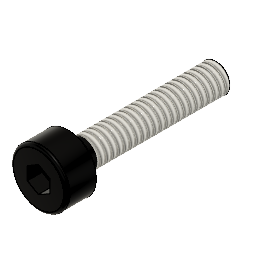
cad of ender 3v3 se head in fusion 360 ffile an .step v7 (Autodesk Fusion 360 archive; units mm, degrees)
design "Tornillo de cabeza hexagonal hueca ISO 4762 - M2 x 10 Acero 4.6 Negro"
description: Tornillo de cabeza hexagonal hueca ISO 4762 - M2 x 10
part number: ISO 4762 - M2 x 10 Acero 4.6 Negro
Autodesk Fusion 360 part; units mm, degrees
sketch "Sketch1" plane through (0, 0, 0) normal (0, 1, 0) x (1, 0, 0)
  line L0 (-1, 0) -> (-1, 10)
  line L1 (-1, 10) -> (0, 10)
  line L2 (0, 10) -> (0, -2)
  line L3 (-1, 0) -> (-1.9, 0)
  line L4 (-1.9, 0) -> (-1.9, -2)
  line L5 (-1.9, -2) -> (0, -2)
  dimension "d9" = 2
  dimension "d66" = 3.8
  dimension "d106" = 2
  dimension "d107" = 10
  constraint perpendicular L0 L1
  constraint collinear origin L1.end L2.end
  constraint perpendicular L0 L3
  constraint coincident origin L3
  constraint vertical L0
  constraint vertical L2
  constraint parallel L2 L4
  constraint coincident L2 L5.end
  constraint perpendicular L2 L5
  measures "d106" distance of L3 L5
  measures "d107" distance of origin L1
revolve "Revolve1" add sketch "Sketch1" angle 360 about axis through (0, 0, -10) along (0, 0, 1)
ref_plane "WorkPlane1" through (0, 0, 2) normal (0, 0, 1) x (1, 0, 0)
sketch "Sketch6" plane through (0, 0, 2) normal (0, 0, 1) x (1, 0, 0)
  line L0 (-0.75, 0) -> (0.75, 0) construction
  line L1 (0, 0) -> (-0.75, 0.433)
  line L2 (-0.75, -0.433) -> (-0.75, 0.433)
  line L3 (-0.75, -0.433) -> (0, 0)
  dimension "d104" = 150
  dimension "d108" = 1.5
  constraint horizontal L0
  constraint midpoint L1.start L0
  constraint coincident L1.start L3.end
  constraint perpendicular L0 L2
  constraint midpoint L0.start L2
  constraint coincident L1.end L2.end
  measures "d104" angle of L0 L1
  measures "d108" distance of L0.end L2
extrude "Extrude1" cut sketch "Sketch6" against normal blind 1
pattern_circular "C-Pattern1" count 6 over 360 about axis through (0, 0, 1.75) along (0, 0, 1) of "Extrude1"
extrude "Extrude2" cut 1 faces at (0, 0.2887, 1) along direction (0, 0, -1) blind 1 draft -85
fillet "Fillet4" radius 0.2 1 edges at (-1.7714, 0.6871, 2)
thread "Thread3" "ISO Metric profile 2.0 M2x0.4 M2x0.4 6g" major diameter 1.9335 minor diameter 1.478 pitch 0.4 angle 60 resizes the face on face at (-0.995, 0.0996, -3.3333) from (0, 0, -1) to (0, 0, -10)
sketch "Sketch7" plane through (0, 0, 0) normal (0, 1, 0) x (1, 0, 0)
  line L0 (-1.02, 10) -> (-1.02, 9.8)
  line L1 (-1.02, 9.8) -> (-0.82, 10)
  line L2 (0, 10) -> (0, -2)
  line L3 (-1.02, 10) -> (0, 10)
  dimension "d101" = 45
  dimension "d112" = 0.2
  dimension "d113" = 1.02
  constraint coincident L2.start L3.end
  constraint perpendicular L2 L3
  constraint coincident L1.end L3
  constraint perpendicular L0 L3
  measures "d101" angle of L0 L1
  measures "d112" distance of L0.end L3
  measures "d113" distance of L0 L2.start
revolve "Revolve3" cut sketch "Sketch7" angle 360 about axis through (0, 0, 1.75) along (0, 0, 1)
equation "d9 = adsk_nomdia"
equation "adsk_nomlen = 10.00 mm"
equation "adsk_headh = 2.00 mm"
equation "adsk_headdia = 3.80 mm"
equation "adsk_nomdia = 2.00 mm"
equation "adsk_philwidth = 1.50 mm"
equation "d31 = -adsk_phildepth"
equation "adsk_phildepth = 1.00 mm"
equation "d66 = adsk_headdia"
equation "d71 = adsk_headh"
equation "d76 = -adsk_phildepth"
equation "adsk_thrlen = 9.00 mm"
equation "d86 = adsk_nomdia * 0.1"
equation "adsk_startang = 45.00 deg"
equation "d101 = adsk_startang"
equation "adsk_pitch1 = 0.40 mm"
equation "adsk_startlen = 0.20 mm"
equation "d106 = adsk_headh"
equation "d107 = adsk_nomlen"
equation "d108 = adsk_philwidth"
equation "d112 = adsk_startlen"
equation "d113 = adsk_nomdia * 0.51"
equation "d115 = min(adsk_thrlen; adsk_nomlen - 0.001 mm)"

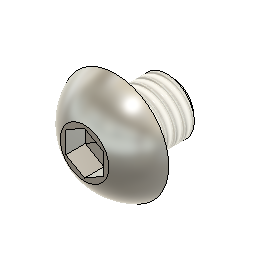
design "Tornillo brochado de cabeza de botón hueca hexagonal ASME B18.3.4M - M3 x 0.5 x 3 Acero grado 2 Normal"
description: Tornillo brochado de cabeza de botón hueca hexagonal ASME B18.3.4M - M3 x 0.5 x 3
part number: BHSBHCS ASME B18.3.4M - M3 x 0.5 x 3 Acero grado 2 Normal
Autodesk Fusion 360 part; units mm, degrees
sketch "Sketch1" plane through (0, 0, 0) normal (0, 1, 0) x (1, 0, 0)
  line L0 (-1.5, 0) -> (-1.5, 3)
  line L1 (-1.5, 3) -> (0, 3)
  line L2 (0, 3) -> (0, -1.65)
  line L3 (-1.5, 0) -> (-2.85, 0)
  line L4 (0, -1.65) -> (-1.3, -1.65)
  arc A0 (-2.85, 0) -> (-1.3, -1.65) centre (0, 1.1242) ccw
  dimension "d9" = 3
  dimension "d66" = 5.7
  dimension "d98" = 2.6
  dimension "d105" = 1.65
  dimension "d106" = 3
  constraint perpendicular L0 L1
  constraint perpendicular L0 L3
  constraint coincident origin L3
  constraint vertical L0
  constraint vertical L2
  constraint coincident origin L2
  constraint perpendicular L2 L4
  constraint coincident L2 A0.centre
  measures "d105" distance of L3 L4
  measures "d106" distance of origin L1
revolve "Revolve1" add sketch "Sketch1" angle 360 about axis through (0, 0, -3) along (0, 0, 1)
ref_plane "WorkPlane1" through (0, 0, 1.65) normal (0, 0, 1) x (1, 0, 0)
sketch "Sketch6" plane through (0, 0, 1.65) normal (0, 0, 1) x (1, 0, 0)
  line L0 (-1, 0) -> (1, 0) construction
  line L1 (0, 0) -> (-1, 0.5774)
  line L2 (-1, -0.5774) -> (-1, 0.5774)
  line L3 (-1, -0.5774) -> (0, 0)
  dimension "d91" = 150
  dimension "d107" = 2
  constraint horizontal L0
  constraint midpoint L1.start L0
  constraint coincident L1.start L3.end
  constraint perpendicular L0 L2
  constraint midpoint L0.start L2
  constraint coincident L1.end L2.end
  measures "d91" angle of L0 L1
  measures "d107" distance of L0.end L2
extrude "Extrude1" cut sketch "Sketch6" against normal blind 1.04
pattern_circular "C-Pattern1" count 6 over 360 about axis through (0, 0, 1.75) along (0, 0, 1) of "Extrude1"
extrude "Extrude2" cut 1 faces at (0, 0, 0.61) along direction (0, 0, -1) blind 1.04 draft -85
fillet "Fillet5" radius 0.1 1 edges at (-1.3985, 0.5424, 0)
thread "Thread5" "ANSI Metric M Profile 3.0 M3x0.5 M3x0.5 4g6g" major diameter 2.927 minor diameter 2.369 pitch 0.5 angle 60 resizes the face on face at (-1.4925, 0.1494, -2.0333) from (0, 0, -1) to (0, 0, -3)
sketch "Sketch5" plane through (0, 0, 0) normal (0, 1, 0) x (1, 0, 0)
  line L0 (0, 3) -> (0, -1.65)
  line L1 (0, 3) -> (-1.53, 3)
  line L2 (-1.53, 3) -> (-1.53, 2.6933)
  line L3 (-1.53, 2.6933) -> (-1.1933, 3)
  dimension "d108" = 0.3067
  dimension "d109" = 1.1933
  dimension "d110" = 1.53
  constraint coincident L0.start L1.start
  constraint perpendicular L1 L2
  constraint coincident L1 L3.end
  measures "d108" distance of L1 L2.end
  measures "d109" distance of L0 L3.end
  measures "d110" distance of L0 L2
revolve "Revolve2" cut sketch "Sketch5" angle 360 about axis through (0, 0, -3) along (0, 0, 1)
equation "d9 = adsk_nomdia"
equation "adsk_nomlen = 3.00 mm"
equation "adsk_headh = 1.65 mm"
equation "adsk_headdia = 5.70 mm"
equation "adsk_nomdia = 3.00 mm"
equation "adsk_philwidth = 2.00 mm"
equation "d31 = -adsk_phildepth"
equation "adsk_phildepth = 1.04 mm"
equation "d66 = adsk_headdia"
equation "d71 = adsk_headh"
equation "d76 = -adsk_phildepth"
equation "adsk_thrlen = 2.00 mm"
equation "adsk_endpointdia = 2.38655 mm"
equation "adsk_startlen = 0.306725 mm"
equation "d98 = adsk_philwidth * 1.3"
equation "adsk_midfillet = 0.10 mm"
equation "d104 = adsk_midfillet"
equation "d105 = adsk_headh"
equation "d106 = adsk_nomlen"
equation "d107 = adsk_philwidth"
equation "d108 = adsk_startlen"
equation "d109 = adsk_endpointdia / 2"
equation "d110 = adsk_nomdia * 0.51"
equation "d116 = min(adsk_thrlen; adsk_nomlen - adsk_midfillet - 0.001 mm)"

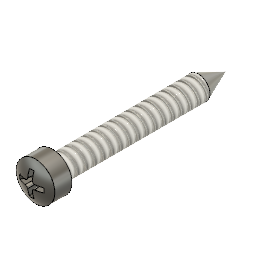
design "Tornillo autorroscante taladrado con hueco cruciforme de tipo I ANSI B18.6.4 2-32 x 0.625 Tipo AB Acero grado 2 Normal"
description: Tornillo autorroscante taladrado con hueco cruciforme de tipo I ANSI B18.6.4 2-32 x 0.625 Tipo AB
part number: CRFHTSTATI ANSI B18.6.4 - 2-32 x 5/8 Acero grado 2 Normal
Autodesk Fusion 360 part; units mm, degrees
sketch "Sketch1" plane through (0, 0, 0) normal (0, 1, 0) x (1, 0, 0)
  line L0 (-1.0922, 0) -> (-1.0922, 15.875)
  line L1 (-1.0922, 15.875) -> (0, 15.875)
  line L2 (0, 15.875) -> (0, -2.1082)
  line L3 (-1.0922, 0) -> (-1.778, 0)
  line L4 (-1.778, 0) -> (-1.778, -1.5748)
  arc A0 (-1.778, -1.5748) -> (0, -2.1082) centre (0, 1.1218) ccw
  dimension "d9" = 2.1844
  dimension "d66" = 3.556
  dimension "d113" = 2.1082
  dimension "d115" = 15.875
  constraint perpendicular L0 L1
  constraint perpendicular L0 L3
  constraint coincident origin L3
  constraint vertical L0
  constraint vertical L2
  constraint coincident L2 A0.centre
  constraint perpendicular L3 L4
  constraint coincident origin L2
  measures "d113" distance of L2.end L3
  measures "d115" distance of origin L1
revolve "Revolve1" add sketch "Sketch1" angle 360 about axis through (0, 0, -15.875) along (0, 0, 1) makes body 1
ref_plane "WorkPlane1" through (0, 0, 2.1082) normal (0, 0, 1) x (1, 0, 0)
sketch "Sketch2" plane through (0, 0, 2.1082) normal (0, 0, 1) x (1, 0, 0)
  line L0 (-0.2159, 0.2159) -> (-1.2446, 0.2159)
  line L1 (-1.2446, 0.2159) -> (-1.2446, -0.2159)
  line L2 (-0.2159, -0.2159) -> (-1.2446, -0.2159)
  line L3 (-0.2159, -0.2159) -> (-0.2159, -1.2446)
  line L4 (-0.2159, -1.2446) -> (0.2159, -1.2446)
  line L5 (0.2159, -0.2159) -> (0.2159, -1.2446)
  line L6 (0.2159, -0.2159) -> (1.2446, -0.2159)
  line L7 (1.2446, -0.2159) -> (1.2446, 0.2159)
  line L8 (0.2159, 0.2159) -> (1.2446, 0.2159)
  line L9 (0.2159, 0.2159) -> (0.2159, 1.2446)
  line L10 (0.2159, 1.2446) -> (-0.2159, 1.2446)
  line L11 (-0.2159, 0.2159) -> (-0.2159, 1.2446)
  point P0 (-1.2446, 0)
  dimension "d107" = 0.4318
  dimension "d109" = 360
  dimension "d110" = 2.4892
  constraint vertical L1
  constraint coincident L1.end L2.end
  constraint midpoint L1 P0
  constraint horizontal L0
  constraint horizontal L2
  constraint vertical L0.start L2.start
  constraint coincident L0.start L11.start
  measures "d107" distance of L0 L2
  measures "d110" distance of L1 L7
extrude "Extrude1" add sketch "Sketch2" against normal blind 1.27 draft -4 separate body makes body 2
draft "Draft1" angle -30 neutral plane through (0, 0, 2.1082) pull (0, 0, 1) 4 faces at (-1.215, -0.0424, 1.6849) (0.0424, -1.215, 1.6849) (1.215, 0.0424, 1.6849) (-0.0424, 1.215, 1.6849) on bodies 2
fillet "Fillet3" radius 0.2159 4 edges at (-0.1715, -0.1715, 1.4732) (-0.1715, 0.1715, 1.4732) (0.1715, 0.1715, 1.4732) (0.1715, -0.1715, 1.4732) on bodies 2
combine "Combine1" operation cut target body 1 tool bodies 2
thread "Thread1" "Inch Tapping Threads 0.086 2-32 2-32 2B" major diameter 2.159 minor diameter 1.5748 pitch 0.7937 angle 60 resizes the face on face at (-1.0908, 0.0544, -5.2917) on bodies 1
sketch "Sketch5" plane through (0, 0, 0) normal (0, 1, 0) x (1, 0, 0)
  line L0 (-1.114, 13.2382) -> (0, 15.875)
  line L1 (-1.114, 13.2382) -> (-1.114, 15.875)
  line L2 (0, 15.875) -> (0, -2.1082)
  line L3 (-1.114, 15.875) -> (0, 15.875)
  dimension "d116" = 1.114
  dimension "d117" = 2.6368
  constraint coincident L0.end L2.start
  constraint coincident L0.end L3
  constraint perpendicular L2 L3
  constraint perpendicular L1 L3
  measures "d116" distance of L1 L0.end
  measures "d117" distance of L0.start L3
revolve "Revolve2" cut sketch "Sketch5" angle 360 about axis through (0, 0, -15.875) along (0, 0, 1) bodies 1
equation "d9 = adsk_nomdia"
equation "d31 = -adsk_phildepth"
equation "d66 = adsk_headdia"
equation "d71 = adsk_headh"
equation "adsk_nomlen = 0.625 in"
equation "adsk_headh = 0.083 in"
equation "adsk_headdia = 0.14 in"
equation "adsk_nomdia = 0.086 in"
equation "adsk_phildia = 0.098 in"
equation "adsk_philwidth = 0.017 in"
equation "adsk_phildepth = 0.05 in"
equation "adsk_startlen = 0.103811 in"
equation "adsk_ovalh = 0.021 in"
equation "d107 = adsk_philwidth"
equation "d110 = adsk_phildia"
equation "d112 = adsk_philwidth / 2"
equation "d113 = adsk_headh"
equation "d114 = ( adsk_headh ) - ( adsk_ovalh )"
equation "d115 = adsk_nomlen"
equation "d116 = adsk_nomdia * 0.51"
equation "d117 = adsk_startlen"

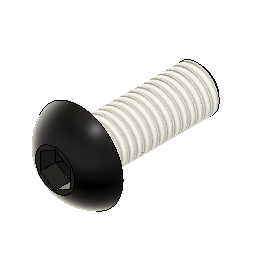
design "Tornillo brochado de cabeza de botón hueca hexagonal ASME B18.3.4M - M3 x 0.5 x 8 Acero grado 2 Negro"
description: Tornillo brochado de cabeza de botón hueca hexagonal ASME B18.3.4M - M3 x 0.5 x 8
part number: BHSBHCS ASME B18.3.4M - M3 x 0.5 x 8 Acero grado 2 Negro
Autodesk Fusion 360 part; units mm, degrees
sketch "Sketch1" plane through (0, 0, 0) normal (0, 1, 0) x (1, 0, 0)
  line L0 (-1.5, 0) -> (-1.5, 8)
  line L1 (-1.5, 8) -> (0, 8)
  line L2 (0, 8) -> (0, -1.65)
  line L3 (-1.5, 0) -> (-2.85, 0)
  line L4 (0, -1.65) -> (-1.3, -1.65)
  arc A0 (-2.85, 0) -> (-1.3, -1.65) centre (0, 1.1242) ccw
  dimension "d9" = 3
  dimension "d66" = 5.7
  dimension "d98" = 2.6
  dimension "d105" = 1.65
  dimension "d106" = 8
  constraint perpendicular L0 L1
  constraint perpendicular L0 L3
  constraint coincident origin L3
  constraint vertical L0
  constraint vertical L2
  constraint coincident origin L2
  constraint perpendicular L2 L4
  constraint coincident L2 A0.centre
  measures "d105" distance of L3 L4
  measures "d106" distance of origin L1
revolve "Revolve1" add sketch "Sketch1" angle 360 about axis through (0, 0, -8) along (0, 0, 1)
ref_plane "WorkPlane1" through (0, 0, 1.65) normal (0, 0, 1) x (1, 0, 0)
sketch "Sketch6" plane through (0, 0, 1.65) normal (0, 0, 1) x (1, 0, 0)
  line L0 (-1, 0) -> (1, 0) construction
  line L1 (0, 0) -> (-1, 0.5774)
  line L2 (-1, -0.5774) -> (-1, 0.5774)
  line L3 (-1, -0.5774) -> (0, 0)
  dimension "d91" = 150
  dimension "d107" = 2
  constraint horizontal L0
  constraint midpoint L1.start L0
  constraint coincident L1.start L3.end
  constraint perpendicular L0 L2
  constraint midpoint L0.start L2
  constraint coincident L1.end L2.end
  measures "d91" angle of L0 L1
  measures "d107" distance of L0.end L2
extrude "Extrude1" cut sketch "Sketch6" against normal blind 1.04
pattern_circular "C-Pattern1" count 6 over 360 about axis through (0, 0, 1.75) along (0, 0, 1) of "Extrude1"
extrude "Extrude2" cut 1 faces at (0, 0, 0.61) along direction (0, 0, -1) blind 1.04 draft -85
fillet "Fillet5" radius 0.1 1 edges at (-1.3985, 0.5424, 0)
thread "Thread5" "ANSI Metric M Profile 3.0 M3x0.5 M3x0.5 4g6g" major diameter 2.927 minor diameter 2.369 pitch 0.5 angle 60 resizes the face on face at (-1.4925, 0.1494, -5.3667) from (0, 0, -1) to (0, 0, -8)
sketch "Sketch5" plane through (0, 0, 0) normal (0, 1, 0) x (1, 0, 0)
  line L0 (0, 8) -> (0, -1.65)
  line L1 (0, 8) -> (-1.53, 8)
  line L2 (-1.53, 8) -> (-1.53, 7.6933)
  line L3 (-1.53, 7.6933) -> (-1.1933, 8)
  dimension "d108" = 0.3067
  dimension "d109" = 1.1933
  dimension "d110" = 1.53
  constraint coincident L0.start L1.start
  constraint perpendicular L1 L2
  constraint coincident L1 L3.end
  measures "d108" distance of L1 L2.end
  measures "d109" distance of L0 L3.end
  measures "d110" distance of L0 L2
revolve "Revolve2" cut sketch "Sketch5" angle 360 about axis through (0, 0, -8) along (0, 0, 1)
equation "d9 = adsk_nomdia"
equation "adsk_nomlen = 8.00 mm"
equation "adsk_headh = 1.65 mm"
equation "adsk_headdia = 5.70 mm"
equation "adsk_nomdia = 3.00 mm"
equation "adsk_philwidth = 2.00 mm"
equation "d31 = -adsk_phildepth"
equation "adsk_phildepth = 1.04 mm"
equation "d66 = adsk_headdia"
equation "d71 = adsk_headh"
equation "d76 = -adsk_phildepth"
equation "adsk_thrlen = 7.00 mm"
equation "adsk_endpointdia = 2.38655 mm"
equation "adsk_startlen = 0.306725 mm"
equation "d98 = adsk_philwidth * 1.3"
equation "adsk_midfillet = 0.10 mm"
equation "d104 = adsk_midfillet"
equation "d105 = adsk_headh"
equation "d106 = adsk_nomlen"
equation "d107 = adsk_philwidth"
equation "d108 = adsk_startlen"
equation "d109 = adsk_endpointdia / 2"
equation "d110 = adsk_nomdia * 0.51"
equation "d116 = min(adsk_thrlen; adsk_nomlen - adsk_midfillet - 0.001 mm)"

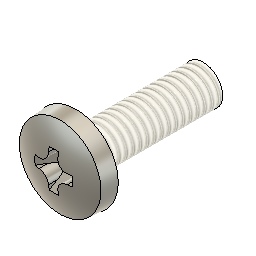
design "Tornillo de fijación JIS B 1111 - M2.5x8 Acero 4.6 Normal"
description: Tornillo de fijación JIS B 1111 - M2.5x8
Autodesk Fusion 360 part; units mm, degrees
sketch "Sketch1" plane through (0, 0, 0) normal (0, 1, 0) x (1, 0, 0)
  line L0 (0, -1.5) -> (0, 8)
  line L1 (-2.65, 0) -> (-2.5625, -1)
  line L2 (-2.65, 0) -> (-1.0691, 0)
  arc A0 (-2.5625, -1) -> (0, -1.5) centre (0, 5.3165) ccw
  line L3 (0, 8) -> (-1.25, 8)
  line L4 (-1.25, 8) -> (-1.25, 0.84)
  line L5 (-1.25, 0.84) -> (-1.0691, 0.165)
  line L6 (-1.0691, 0.165) -> (-1.0691, 0)
  dimension "d13" = 5
  dimension "d14" = 5.3
  dimension "d18" = 2.5
  dimension "d23" = 15
  dimension "d53" = 1.5
  dimension "d55" = 7.16
  dimension "d56" = 8
  dimension "d57" = 7.835
  dimension "d60" = 1
  constraint vertical L0
  constraint coincident origin L0
  constraint horizontal L2
  constraint coincident origin L2
  constraint coincident L0 A0.end
  constraint coincident L0 A0.centre
  constraint coincident L0.start A0.end
  constraint perpendicular L0 L3
  constraint perpendicular L3 L4
  constraint vertical L6
  constraint coincident L2.end L6.end
  measures "d13" angle of L0 L1
  measures "d23" angle of L4 L5
  measures "d53" distance of L0.start L2
  measures "d55" distance of L3 L4.end
  measures "d56" distance of L2 L3
  measures "d57" distance of L3 L5.end
  measures "d60" distance of L1.end L2
revolve "Revolve1" add sketch "Sketch1" angle 360 about axis through (0, 0, 1.5) along (0, 0, -1) makes body 1
fillet "Fillet2" radius 0.1 1 edges at (-0.9968, 0.3866, 0) on bodies 1
ref_plane "WorkPlane1" through (0, 0, 1.5) normal (0, 0, 1) x (1, 0, 0)
sketch "Sketch2" plane through (0, 0, 1.5) normal (0, 0, 1) x (1, 0, 0)
  line L0 (-1.25, 0) -> (1.25, 0) construction
  line L1 (0, -1.25) -> (0, 1.25) construction
  line L2 (-0.296, 1.25) -> (0.296, 1.25)
  line L3 (0.296, 1.25) -> (0.296, 0.296)
  line L4 (0.296, 0.296) -> (1.25, 0.296)
  line L5 (1.25, 0.296) -> (1.25, -0.296)
  line L6 (1.25, -0.296) -> (0.296, -0.296)
  line L7 (0.296, -0.296) -> (0.296, -1.25)
  line L8 (0.296, -1.25) -> (-0.296, -1.25)
  line L9 (-0.296, -1.25) -> (-0.296, -0.296)
  line L10 (-0.296, -0.296) -> (-1.25, -0.296)
  line L11 (-1.25, -0.296) -> (-1.25, 0.296)
  line L12 (-1.25, 0.296) -> (-0.296, 0.296)
  line L13 (-0.296, 0.296) -> (-0.296, 1.25)
  dimension "d58" = 0.592
  dimension "d59" = 0.592
  dimension "d61" = 2.5
  dimension "d62" = 2.5
  constraint horizontal L0
  constraint vertical L1
  constraint midpoint L0 L1
  constraint midpoint origin L1
  constraint perpendicular L1 L2
  constraint perpendicular L2 L3
  constraint perpendicular L3 L4
  constraint perpendicular L0 L5
  constraint perpendicular L5 L6
  constraint perpendicular L0 L7
  constraint perpendicular L7 L8
  constraint perpendicular L8 L9
  constraint perpendicular L7 L10
  constraint perpendicular L10 L11
  constraint perpendicular L11 L12
  constraint vertical L13
  constraint coincident L9 L12.end
  constraint coincident L3.end L7
  constraint coincident L6 L9.end
  constraint coincident L4 L12.end
  constraint midpoint L0.end L5
  constraint midpoint L1.start L8
  constraint midpoint L1.end L2
  constraint midpoint L0.start L11
  measures "d58" distance of L10 L12
  measures "d59" distance of L3 L13
  measures "d61" distance of L2 L8
  measures "d62" distance of L5 L11
extrude "Extrude1" add sketch "Sketch2" against normal blind 1.32 separate body makes body 2
draft "Draft1" angle -30 neutral plane through (0, 0, 1.5) pull (0, 0, 1) 4 faces at (0.0987, -1.25, 1.06) (-0.0987, 1.25, 1.06) (-1.25, -0.0987, 1.06) (1.25, 0.0987, 1.06) on bodies 2
fillet "Fillet1" radius 0.592 4 edges at (0.296, -0.296, 0.84) (-0.296, -0.296, 0.84) (-0.296, 0.296, 0.84) (0.296, 0.296, 0.84) on bodies 2
combine "Combine1" operation cut target body 1 tool bodies 2
thread "Thread1" "ISO Metric profile 2.5 M2.5x0.45 M2.5x0.45 6g" major diameter 2.43 minor diameter 1.9165 pitch 0.45 angle 60 resizes the face on face at (-1.2484, -0.0623, -5.6133) on bodies 1
equation "adsk_nomdia = 2.50 mm"
equation "adsk_nomlen = 8.00 mm"
equation "adsk_headdia = 5.30 mm"
equation "adsk_baseh = 1.00 mm"
equation "adsk_phildia = 2.50 mm"
equation "adsk_midfillet = 0.10 mm"
equation "adsk_thrlen = 7.16 mm"
equation "adsk_phildepth = 1.32 mm"
equation "adsk_thrrun = 0.675 mm"
equation "adsk_thrang = 15.00 deg"
equation "adsk_headang = 5.00 deg"
equation "d13 = adsk_headang"
equation "d14 = adsk_headdia"
equation "adsk_ovalh = 0.50 mm"
equation "d18 = adsk_nomdia"
equation "d23 = adsk_thrang"
equation "d32 = adsk_baseh + adsk_ovalh"
equation "adsk_philwidth = 0.592 mm"
equation "d43 = -adsk_phildepth"
equation "d48 = adsk_philwidth"
equation "d52 = adsk_midfillet"
equation "d53 = adsk_baseh + adsk_ovalh"
equation "d55 = adsk_thrlen"
equation "d56 = adsk_nomlen"
equation "d57 = adsk_thrlen + adsk_thrrun"
equation "d58 = adsk_philwidth"
equation "d59 = adsk_philwidth"
equation "d60 = adsk_baseh"
equation "d61 = adsk_phildia"
equation "d62 = adsk_phildia"

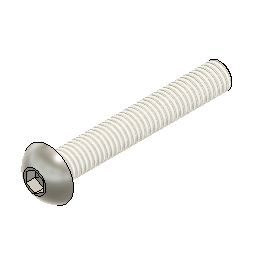
design "Tornillo brochado de cabeza de botón hueca hexagonal ASME B18.3.4M - M3 x 0.5 x 20 Acero grado 2 Normal"
description: Tornillo brochado de cabeza de botón hueca hexagonal ASME B18.3.4M - M3 x 0.5 x 20
part number: BHSBHCS ASME B18.3.4M - M3 x 0.5 x 20 Acero grado 2 Normal
Autodesk Fusion 360 part; units mm, degrees
sketch "Sketch1" plane through (0, 0, 0) normal (0, 1, 0) x (1, 0, 0)
  line L0 (-1.5, 0) -> (-1.5, 20)
  line L1 (-1.5, 20) -> (0, 20)
  line L2 (0, 20) -> (0, -1.65)
  line L3 (-1.5, 0) -> (-2.85, 0)
  line L4 (0, -1.65) -> (-1.3, -1.65)
  arc A0 (-2.85, 0) -> (-1.3, -1.65) centre (0, 1.1242) ccw
  dimension "d9" = 3
  dimension "d66" = 5.7
  dimension "d98" = 2.6
  dimension "d105" = 1.65
  dimension "d106" = 20
  constraint perpendicular L0 L1
  constraint perpendicular L0 L3
  constraint coincident origin L3
  constraint vertical L0
  constraint vertical L2
  constraint coincident origin L2
  constraint perpendicular L2 L4
  constraint coincident L2 A0.centre
  measures "d105" distance of L3 L4
  measures "d106" distance of origin L1
revolve "Revolve1" add sketch "Sketch1" angle 360 about axis through (0, 0, -20) along (0, 0, 1)
ref_plane "WorkPlane1" through (0, 0, 1.65) normal (0, 0, 1) x (1, 0, 0)
sketch "Sketch6" plane through (0, 0, 1.65) normal (0, 0, 1) x (1, 0, 0)
  line L0 (-1, 0) -> (1, 0) construction
  line L1 (0, 0) -> (-1, 0.5774)
  line L2 (-1, -0.5774) -> (-1, 0.5774)
  line L3 (-1, -0.5774) -> (0, 0)
  dimension "d91" = 150
  dimension "d107" = 2
  constraint horizontal L0
  constraint midpoint L1.start L0
  constraint coincident L1.start L3.end
  constraint perpendicular L0 L2
  constraint midpoint L0.start L2
  constraint coincident L1.end L2.end
  measures "d91" angle of L0 L1
  measures "d107" distance of L0.end L2
extrude "Extrude1" cut sketch "Sketch6" against normal blind 1.04
pattern_circular "C-Pattern1" count 6 over 360 about axis through (0, 0, 1.75) along (0, 0, 1) of "Extrude1"
extrude "Extrude2" cut 1 faces at (0, 0, 0.61) along direction (0, 0, -1) blind 1.04 draft -85
fillet "Fillet5" radius 0.1 1 edges at (-1.3985, 0.5424, 0)
thread "Thread5" "ANSI Metric M Profile 3.0 M3x0.5 M3x0.5 4g6g" major diameter 2.927 minor diameter 2.369 pitch 0.5 angle 60 resizes the face on face at (-1.4925, 0.1494, -6.7333) from (0, 0, -1) to (0, 0, -20)
sketch "Sketch5" plane through (0, 0, 0) normal (0, 1, 0) x (1, 0, 0)
  line L0 (0, 20) -> (0, -1.65)
  line L1 (0, 20) -> (-1.53, 20)
  line L2 (-1.53, 20) -> (-1.53, 19.6933)
  line L3 (-1.53, 19.6933) -> (-1.1933, 20)
  dimension "d108" = 0.3067
  dimension "d109" = 1.1933
  dimension "d110" = 1.53
  constraint coincident L0.start L1.start
  constraint perpendicular L1 L2
  constraint coincident L1 L3.end
  measures "d108" distance of L1 L2.end
  measures "d109" distance of L0 L3.end
  measures "d110" distance of L0 L2
revolve "Revolve2" cut sketch "Sketch5" angle 360 about axis through (0, 0, -20) along (0, 0, 1)
equation "d9 = adsk_nomdia"
equation "adsk_nomlen = 20.00 mm"
equation "adsk_headh = 1.65 mm"
equation "adsk_headdia = 5.70 mm"
equation "adsk_nomdia = 3.00 mm"
equation "adsk_philwidth = 2.00 mm"
equation "d31 = -adsk_phildepth"
equation "adsk_phildepth = 1.04 mm"
equation "d66 = adsk_headdia"
equation "d71 = adsk_headh"
equation "d76 = -adsk_phildepth"
equation "adsk_thrlen = 19.00 mm"
equation "adsk_endpointdia = 2.38655 mm"
equation "adsk_startlen = 0.306725 mm"
equation "d98 = adsk_philwidth * 1.3"
equation "adsk_midfillet = 0.10 mm"
equation "d104 = adsk_midfillet"
equation "d105 = adsk_headh"
equation "d106 = adsk_nomlen"
equation "d107 = adsk_philwidth"
equation "d108 = adsk_startlen"
equation "d109 = adsk_endpointdia / 2"
equation "d110 = adsk_nomdia * 0.51"
equation "d116 = min(adsk_thrlen; adsk_nomlen - adsk_midfillet - 0.001 mm)"

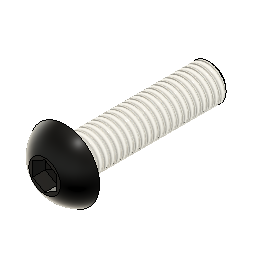
design "Tornillo brochado de cabeza de botón hueca hexagonal ASME B18.3.4M - M3 x 0.5 x 12 Acero grado 2 Negro"
description: Tornillo brochado de cabeza de botón hueca hexagonal ASME B18.3.4M - M3 x 0.5 x 12
part number: BHSBHCS ASME B18.3.4M - M3 x 0.5 x 12 Acero grado 2 Negro
Autodesk Fusion 360 part; units mm, degrees
sketch "Sketch1" plane through (0, 0, 0) normal (0, 1, 0) x (1, 0, 0)
  line L0 (-1.5, 0) -> (-1.5, 12)
  line L1 (-1.5, 12) -> (0, 12)
  line L2 (0, 12) -> (0, -1.65)
  line L3 (-1.5, 0) -> (-2.85, 0)
  line L4 (0, -1.65) -> (-1.3, -1.65)
  arc A0 (-2.85, 0) -> (-1.3, -1.65) centre (0, 1.1242) ccw
  dimension "d9" = 3
  dimension "d66" = 5.7
  dimension "d98" = 2.6
  dimension "d105" = 1.65
  dimension "d106" = 12
  constraint perpendicular L0 L1
  constraint perpendicular L0 L3
  constraint coincident origin L3
  constraint vertical L0
  constraint vertical L2
  constraint coincident origin L2
  constraint perpendicular L2 L4
  constraint coincident L2 A0.centre
  measures "d105" distance of L3 L4
  measures "d106" distance of origin L1
revolve "Revolve1" add sketch "Sketch1" angle 360 about axis through (0, 0, -12) along (0, 0, 1)
ref_plane "WorkPlane1" through (0, 0, 1.65) normal (0, 0, 1) x (1, 0, 0)
sketch "Sketch6" plane through (0, 0, 1.65) normal (0, 0, 1) x (1, 0, 0)
  line L0 (-1, 0) -> (1, 0) construction
  line L1 (0, 0) -> (-1, 0.5774)
  line L2 (-1, -0.5774) -> (-1, 0.5774)
  line L3 (-1, -0.5774) -> (0, 0)
  dimension "d91" = 150
  dimension "d107" = 2
  constraint horizontal L0
  constraint midpoint L1.start L0
  constraint coincident L1.start L3.end
  constraint perpendicular L0 L2
  constraint midpoint L0.start L2
  constraint coincident L1.end L2.end
  measures "d91" angle of L0 L1
  measures "d107" distance of L0.end L2
extrude "Extrude1" cut sketch "Sketch6" against normal blind 1.04
pattern_circular "C-Pattern1" count 6 over 360 about axis through (0, 0, 1.75) along (0, 0, 1) of "Extrude1"
extrude "Extrude2" cut 1 faces at (0, 0, 0.61) along direction (0, 0, -1) blind 1.04 draft -85
fillet "Fillet5" radius 0.1 1 edges at (-1.3985, 0.5424, 0)
thread "Thread5" "ANSI Metric M Profile 3.0 M3x0.5 M3x0.5 4g6g" major diameter 2.927 minor diameter 2.369 pitch 0.5 angle 60 resizes the face on face at (-1.4925, 0.1494, -8.0333) from (0, 0, -1) to (0, 0, -12)
sketch "Sketch5" plane through (0, 0, 0) normal (0, 1, 0) x (1, 0, 0)
  line L0 (0, 12) -> (0, -1.65)
  line L1 (0, 12) -> (-1.53, 12)
  line L2 (-1.53, 12) -> (-1.53, 11.6933)
  line L3 (-1.53, 11.6933) -> (-1.1933, 12)
  dimension "d108" = 0.3067
  dimension "d109" = 1.1933
  dimension "d110" = 1.53
  constraint coincident L0.start L1.start
  constraint perpendicular L1 L2
  constraint coincident L1 L3.end
  measures "d108" distance of L1 L2.end
  measures "d109" distance of L0 L3.end
  measures "d110" distance of L0 L2
revolve "Revolve2" cut sketch "Sketch5" angle 360 about axis through (0, 0, -12) along (0, 0, 1)
equation "d9 = adsk_nomdia"
equation "adsk_nomlen = 12.00 mm"
equation "adsk_headh = 1.65 mm"
equation "adsk_headdia = 5.70 mm"
equation "adsk_nomdia = 3.00 mm"
equation "adsk_philwidth = 2.00 mm"
equation "d31 = -adsk_phildepth"
equation "adsk_phildepth = 1.04 mm"
equation "d66 = adsk_headdia"
equation "d71 = adsk_headh"
equation "d76 = -adsk_phildepth"
equation "adsk_thrlen = 11.00 mm"
equation "adsk_endpointdia = 2.38655 mm"
equation "adsk_startlen = 0.306725 mm"
equation "d98 = adsk_philwidth * 1.3"
equation "adsk_midfillet = 0.10 mm"
equation "d104 = adsk_midfillet"
equation "d105 = adsk_headh"
equation "d106 = adsk_nomlen"
equation "d107 = adsk_philwidth"
equation "d108 = adsk_startlen"
equation "d109 = adsk_endpointdia / 2"
equation "d110 = adsk_nomdia * 0.51"
equation "d116 = min(adsk_thrlen; adsk_nomlen - adsk_midfillet - 0.001 mm)"

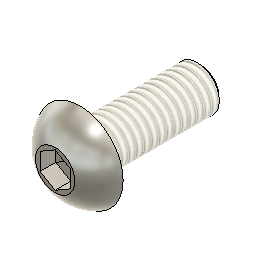
design "Tornillo brochado de cabeza de botón hueca hexagonal ASME B18.3.4M - M3 x 0.5 x 8 Acero grado 2 Normal"
description: Tornillo brochado de cabeza de botón hueca hexagonal ASME B18.3.4M - M3 x 0.5 x 8
part number: BHSBHCS ASME B18.3.4M - M3 x 0.5 x 8 Acero grado 2 Normal
Autodesk Fusion 360 part; units mm, degrees
sketch "Sketch1" plane through (0, 0, 0) normal (0, 1, 0) x (1, 0, 0)
  line L0 (-1.5, 0) -> (-1.5, 8)
  line L1 (-1.5, 8) -> (0, 8)
  line L2 (0, 8) -> (0, -1.65)
  line L3 (-1.5, 0) -> (-2.85, 0)
  line L4 (0, -1.65) -> (-1.3, -1.65)
  arc A0 (-2.85, 0) -> (-1.3, -1.65) centre (0, 1.1242) ccw
  dimension "d9" = 3
  dimension "d66" = 5.7
  dimension "d98" = 2.6
  dimension "d105" = 1.65
  dimension "d106" = 8
  constraint perpendicular L0 L1
  constraint perpendicular L0 L3
  constraint coincident origin L3
  constraint vertical L0
  constraint vertical L2
  constraint coincident origin L2
  constraint perpendicular L2 L4
  constraint coincident L2 A0.centre
  measures "d105" distance of L3 L4
  measures "d106" distance of origin L1
revolve "Revolve1" add sketch "Sketch1" angle 360 about axis through (0, 0, -8) along (0, 0, 1)
ref_plane "WorkPlane1" through (0, 0, 1.65) normal (0, 0, 1) x (1, 0, 0)
sketch "Sketch6" plane through (0, 0, 1.65) normal (0, 0, 1) x (1, 0, 0)
  line L0 (-1, 0) -> (1, 0) construction
  line L1 (0, 0) -> (-1, 0.5774)
  line L2 (-1, -0.5774) -> (-1, 0.5774)
  line L3 (-1, -0.5774) -> (0, 0)
  dimension "d91" = 150
  dimension "d107" = 2
  constraint horizontal L0
  constraint midpoint L1.start L0
  constraint coincident L1.start L3.end
  constraint perpendicular L0 L2
  constraint midpoint L0.start L2
  constraint coincident L1.end L2.end
  measures "d91" angle of L0 L1
  measures "d107" distance of L0.end L2
extrude "Extrude1" cut sketch "Sketch6" against normal blind 1.04
pattern_circular "C-Pattern1" count 6 over 360 about axis through (0, 0, 1.75) along (0, 0, 1) of "Extrude1"
extrude "Extrude2" cut 1 faces at (0, 0, 0.61) along direction (0, 0, -1) blind 1.04 draft -85
fillet "Fillet5" radius 0.1 1 edges at (-1.3985, 0.5424, 0)
thread "Thread5" "ANSI Metric M Profile 3.0 M3x0.5 M3x0.5 4g6g" major diameter 2.927 minor diameter 2.369 pitch 0.5 angle 60 resizes the face on face at (-1.4925, 0.1494, -5.3667) from (0, 0, -1) to (0, 0, -8)
sketch "Sketch5" plane through (0, 0, 0) normal (0, 1, 0) x (1, 0, 0)
  line L0 (0, 8) -> (0, -1.65)
  line L1 (0, 8) -> (-1.53, 8)
  line L2 (-1.53, 8) -> (-1.53, 7.6933)
  line L3 (-1.53, 7.6933) -> (-1.1933, 8)
  dimension "d108" = 0.3067
  dimension "d109" = 1.1933
  dimension "d110" = 1.53
  constraint coincident L0.start L1.start
  constraint perpendicular L1 L2
  constraint coincident L1 L3.end
  measures "d108" distance of L1 L2.end
  measures "d109" distance of L0 L3.end
  measures "d110" distance of L0 L2
revolve "Revolve2" cut sketch "Sketch5" angle 360 about axis through (0, 0, -8) along (0, 0, 1)
equation "d9 = adsk_nomdia"
equation "adsk_nomlen = 8.00 mm"
equation "adsk_headh = 1.65 mm"
equation "adsk_headdia = 5.70 mm"
equation "adsk_nomdia = 3.00 mm"
equation "adsk_philwidth = 2.00 mm"
equation "d31 = -adsk_phildepth"
equation "adsk_phildepth = 1.04 mm"
equation "d66 = adsk_headdia"
equation "d71 = adsk_headh"
equation "d76 = -adsk_phildepth"
equation "adsk_thrlen = 7.00 mm"
equation "adsk_endpointdia = 2.38655 mm"
equation "adsk_startlen = 0.306725 mm"
equation "d98 = adsk_philwidth * 1.3"
equation "adsk_midfillet = 0.10 mm"
equation "d104 = adsk_midfillet"
equation "d105 = adsk_headh"
equation "d106 = adsk_nomlen"
equation "d107 = adsk_philwidth"
equation "d108 = adsk_startlen"
equation "d109 = adsk_endpointdia / 2"
equation "d110 = adsk_nomdia * 0.51"
equation "d116 = min(adsk_thrlen; adsk_nomlen - adsk_midfillet - 0.001 mm)"

design "High-speed M6 Nozzle for Ender-3V3 SE/Ender-5 S1}"
Autodesk Fusion 360 part; units mm, degrees
sketch "Boceto1" plane through (0, 0, 0) normal (1, 0, 0) x (0, 1, 0)
  line L0 (0, 0) -> (0, -9)
  line L1 (0, 0) -> (0, -8)
  line L2 (-3, 0) -> (3, 0)
  line L3 (0, 0) -> (0, -16.8)
  dimension "d2" = 9
  dimension "d3" = 8
  dimension "d4" = 16.8
  constraint vertical L0
  constraint coincident L0.start L1.start
  constraint parallel L0 L1
  constraint perpendicular L0 L2
  constraint perpendicular L2 L3
  measures "d2" distance of L0.start L0.end
  measures "d3" distance of L0.start L1.end
  measures "d4" distance of L0.start L3.end
sketch "Boceto3" plane through (0, 0, 0) normal (1, 0, 0) x (0, 0, -1)
  line L0 (16.7895, -0.4) -> (16.7895, 0)
  line L1 (-0.0105, -3) -> (-0.0105, 0)
  line L2 (-0.0105, -3) -> (7.4895, -3)
  line L3 (16.7895, -0.4) -> (14.7995, -1.5275)
  line L4 (14.7995, -1.5275) -> (14.6156, -1.9779)
  line L5 (13.7456, -2.5) -> (14.6156, -1.9779)
  line L6 (12.9556, -2.5) -> (13.7456, -2.5)
  line L7 (12.1144, -3.464) -> (12.9556, -2.5)
  line L8 (12.1144, -3.464) -> (9, -3.464)
  line L9 (9, -2.5) -> (9, -3.464)
  line L10 (9, -2.5) -> (8, -2.5)
  line L11 (8, -2.5) -> (7.4895, -3)
  line L12 (8, 0) -> (8, -2.5) construction
  line L13 (9, 0) -> (9, -2.5) construction
  line L14 (12.9556, 2.5) -> (13.7456, 2.5)
  line L15 (9, 0) -> (9, 2.5) construction
  line L16 (-0.0105, 3) -> (7.4895, 3)
  line L17 (16.7895, 0.4) -> (14.7995, 1.5275)
  line L18 (12.1144, 3.464) -> (12.9556, 2.5)
  line L19 (-0.0105, 3) -> (-0.0105, 0)
  line L20 (9, 2.5) -> (8, 2.5)
  line L21 (12.1144, 3.464) -> (9, 3.464)
  line L22 (14.7995, 1.5275) -> (14.6156, 1.9779)
  line L23 (8, 2.5) -> (7.4895, 3)
  line L24 (8, 0) -> (8, 2.5) construction
  line L25 (13.7456, 2.5) -> (14.6156, 1.9779)
  line L26 (16.7895, 0.4) -> (16.7895, 0)
  line L27 (9, 2.5) -> (9, 3.464)
  line L28 (16.7895, -0.2) -> (-0.7895, -0.2)
  line L29 (-0.7895, -0.2) -> (-0.7895, 0.2)
  line L30 (-0.7895, 0.2) -> (16.7895, 0.2)
  line L31 (16.7895, 0.2) -> (16.7895, -0.2)
  line L32 (16.7895, -0.2) -> (-0.7895, 0.2) construction
  line L33 (-0.7895, -0.2) -> (16.7895, 0.2) construction
  line L34 (8, 2.5) -> (7.4895, 3)
  line L35 (8, -2.5) -> (8, -3)
  line L36 (8, -3) -> (7.4895, -3)
  line L37 (8, 2.5) -> (7.4895, 3)
  point P0 (9, 0)
  point P1 (9, 0)
  point P2 (8, 0)
  point P3 (8, 0)
  dimension "d6" = 3
  dimension "d7" = 16.8
  dimension "d10" = 0.4
  dimension "d12" = 0.79
  dimension "d13" = 0.4504
  dimension "d14" = 0.87
  dimension "d15" = 1.99
  dimension "d19" = 7.5
  constraint vertical L1
  constraint vertical L0
  constraint perpendicular L8 L9
  constraint perpendicular L9 L10
  constraint perpendicular L10 L12
  constraint coincident P1 P0
  constraint horizontal L28
  constraint perpendicular L28 L29
  constraint parallel L28 L30
  constraint parallel L29 L31
  constraint coincident L32 P3
  constraint coincident L33 P3
  constraint midpoint L0 L28.start
  constraint coincident P3 P2
  constraint perpendicular L10 L35
  measures "d6" distance of L1.end L1.start
  measures "d7" distance of L0.end L1.end
  measures "d10" distance of L0.end L0.start
  measures "d12" distance of L5.start L6.start
  measures "d13" vertical distance of L3.end L4.end
  measures "d14" horizontal distance of L4.end L5.start
  measures "d15" horizontal distance of L0.start L3.end
  measures "d19" distance of L2.end L1.start
revolve "Revolución1" add sketch "Boceto3" angle 360 about axis through (0, 0, 1.75) along (0, 0, 1) contours L0 L1 L2 L3 L4 L5 L6 L7 L8 L9 L10 L11 L28 makes body 1
sketch "Boceto4" plane through (0, 0, -9) normal (0, 0, 1) x (-1, 0, 0)
  circle A0 centre (0, 0) radius 3.464
  circle A1 centre (0, 0) radius 2.5
  line L0 (3.464, 0) -> (1.732, 2.9999)
  line L1 (1.732, 2.9999) -> (-1.732, 2.9999)
  line L2 (-1.732, 2.9999) -> (-3.464, 0)
  line L3 (-3.464, 0) -> (-1.732, -2.9999)
  line L4 (-1.732, -2.9999) -> (1.732, -2.9999)
  line L5 (1.732, -2.9999) -> (3.464, 0)
  constraint coincident A0 L0.start
  constraint coincident A0.centre A1.centre
extrude "Extruir1" cut sketch "Boceto4" against normal blind 7 contours A0 L0 | A0 L5 | A0 L1 | A0 L4 | A0 L2 | A0 L3 bodies 1
sketch "Boceto5" plane through (0, 0, 0.0105) normal (0, 0, 1) x (-1, 0, 0)
  circle A0 centre (0, 0) radius 0.2
  circle A1 centre (0, 0) radius 1
  circle A2 centre (0, 0) radius 3
  dimension "d26" = 2
  constraint concentric A0 A1
  measures "d26" diameter of A1
hole "Agujero1" at (0, 0, 0.0105) direction (0, 0, -1) diameter 2 depth 15 tip angle 45 bodies 1
chamfer "Chaflán1" distance 0.5 angle 45 1 edges at (-0.9323, 0.3616, 0.0105) on bodies 1
chamfer "Chaflán2" distance 0.3 angle 45 1 edges at (-2.797, -1.0848, 0.0105) on bodies 1
sketch "Boceto6" plane through (0, -2.9999, 0) normal (0, -1, 0) x (1, 0, 0)
  spline S0 degree 2 poles (1.732, -12.1144) (0, -12.87) (-1.732, -12.1144) knots 0 0 0 0.355742 0.355742 0.355742 weights 1 1.154701 1
  line L0 (1.732, -12.1144) -> (1.732, -9)
  line L1 (1.732, -9) -> (-1.732, -9)
  line L2 (-1.732, -9) -> (-1.732, -12.1144)
  line L3 (-1.732, -12.1144) -> (1.732, -12.1144) construction
  line L4 (1.732, -12.1144) -> (1.732, -9) construction
  line L5 (1.732, -9) -> (-1.732, -9) construction
  line L6 (-1.732, -9) -> (-1.732, -12.1144) construction
  dimension "d32" = 1.5
  text T0 "0.4" font "Arial" height 1.5 align centre middle in box 3.464 x 3.1144 at (-1.732, -12.1144) x (1, 0) y (0, 1) spacing 1 kerned
  constraint coincident S0.start
  constraint coincident L1.end
extrude "Extruir2" add sketch "Boceto6" along normal blind 0.01 text T0 bodies 1
sketch "Boceto7" plane through (0, 0, 0.0105) normal (0, 0, 1) x (-1, 0, 0)
  circle A0 centre (0, 0) radius 1.5
  circle A1 centre (0, 0) radius 2.7
  circle A2 centre (0, 0) radius 3.5
  circle A3 centre (0, 0) radius 3
  constraint coincident A0.centre A1.centre
extrude "Extruir3" add sketch "Boceto7" against normal blind 8 separate body contours A2 makes body 2
extrude "Extruir4" add 1 faces at (-3.3091, 0.3229, -7.9895) along direction (0, 0, -1) blind 1.5 on bodies 2 bodies 2
chamfer "Chaflán3" distance 0.5 angle 45 1 edges at (2.797, 1.0848, -9.4895) on bodies 2
ref_plane "PlanoDeObra1" through (0, 0, -8.9895) normal (0, 0, 1) x (-1, 0, 0)
split "Dividir1" by plane through (0, 0, -8.9895) normal (0, 0, 1) bodies 2 makes body 3 at (-3.4826, 0.3485, -2.9895)
thread "Rosca2" "ISO Metric profile 6.0 M6x1 M6x1 6H" major diameter 6.147 minor diameter 5.035 pitch 1 angle 60 modelled right hand crest width 0.2748 on face at (-2.9963, 0.1495, -5.9895) crest through (-2.5175, 0, -0.2395) on bodies 3
combine "Combinar2" operation add target body 3 tool bodies 2
combine "Combinar1" operation cut target body 1 tool bodies 3
